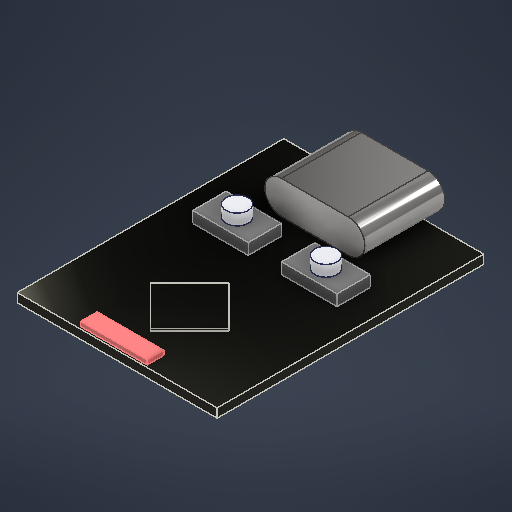
# Autodesk Inventor part: esp32-c3-supermini
Saved by Autodesk Inventor 2027.1 (Build 311270010, 270A)
## iProperties
Created: 2026-09-27
Part Number: esp32-c3-supermini
Material: 열가소성 수지
Document SubType Name: Modeling
Designer: work
Density: 1.28 g/cm^3
Appearance: 매끄러움 - 검은색
Author: work
Autodesk Inventor part; units mm, degrees
ref_plane "YZ Plane" through (0, 0, 0) normal (1, 0, 0) x (0, 1, 0)
ref_plane "XZ Plane" through (0, 0, 0) normal (0, 1, 0) x (-1, 0, 0)
sketch "스케치1" plane through (0, 0, 0) normal (0, 1, 0) x (-1, 0, 0)
  line L0 (0, 0) -> (18, 0)
  line L1 (18, 0) -> (18, -24)
  line L2 (18, -24) -> (0, -24)
  line L3 (0, -24) -> (0, 0)
  dimension "d0" = 18
  dimension "d1" = 24
  constraints: 8 end point, 2 parallel, 1 horizontal, 1 perpendicular
  measures "d0" distance of L1.end L2.end
  measures "d1" distance of L0.end L1.end
extrude "돌출1" add sketch "스케치1" along normal blind 0.8
ref_plane "작업 평면1" through (0, 0, -25) normal (0, 0, -1) x (-1, 0, 0)
sketch "스케치2" plane through (0, 0, -25) normal (0, 0, -1) x (-1, 0, 0)
  line L0 (6, 2.3) -> (12, 2.3) construction
  line L1 (6, 0.8) -> (12, 0.8)
  line L2 (12, 3.8) -> (6, 3.8)
  arc A0 (6, 3.8) -> (6, 0.8) centre (6, 2.3) ccw
  arc A1 (12, 0.8) -> (12, 3.8) centre (12, 2.3) ccw
  line L3 (0, 0.8) -> (18, 0.8) projected
  line L4 (6, 3.6) -> (12, 3.6)
  arc A2 (12, 1) -> (12, 3.6) centre (12, 2.3) ccw
  line L5 (12, 1) -> (6, 1)
  arc A3 (6, 3.6) -> (6, 1) centre (6, 2.3) ccw
  point P0 (0, 0)
  point P1 (9, 2.3)
  point P2 (4.5, 2.3)
  point P3 (13.5, 2.3)
  point P4 (9, 0.8)
  dimension "d5" = 3
  dimension "d6" = 9
  dimension "d7" = 0.2
  constraints: 12 end point, 10 point on circle, 4 centre point, 4 tangent, 3 midpoint, 2 parallel, 1 horizontal, 3 other
  measures "d5" distance between parallel lines of L1 L2
  measures "d6" distance of point (4.5, 2.3) point (13.5, 2.3)
  measures "d7" distance between parallel lines of L2 L4
extrude "돌출2" add sketch "스케치2" against normal blind 7 separate body
sketch "스케치3" plane through (0, 0, -18) normal (0, 0, 1) x (1, 0, 0)
  line L0 (-6, 3.8) -> (-12, 3.8) projected
  arc A0 (-6, 0.8) -> (-6, 3.8) centre (-6, 2.3) ccw projected
  line L1 (-6, 3.8) -> (-12, 3.8) projected
  arc A1 (-12, 3.8) -> (-12, 0.8) centre (-12, 2.3) ccw projected
  line L2 (-12, 0.8) -> (-6, 0.8) projected
  line L3 (-6, 1) -> (-12, 1) projected
  arc A2 (-12, 3.6) -> (-12, 1) centre (-12, 2.3) ccw projected
  line L4 (-12, 3.6) -> (-6, 3.6) projected
  arc A3 (-6, 1) -> (-6, 3.6) centre (-6, 2.3) ccw projected
  point P0 (0, 0)
extrude "돌출3" add sketch "스케치3" along normal blind 0.2 contours A0 L2 A1 L0 | L3 A2 L4 A3 bodies 2
sketch "스케치4" plane through (0, 0.8, 0) normal (0, 1, 0) x (1, 0, 0)
  line L0 (-9, 10.0711) -> (-12.5355, 6.5355)
  line L1 (-12.5355, 6.5355) -> (-9, 3)
  line L2 (-9, 3) -> (-5.4645, 6.5355)
  line L3 (-5.4645, 6.5355) -> (-9, 10.0711)
  line L4 (-9, 10.0711) -> (-4, 10.0711) construction
  line L5 (-18, 0) -> (0, 0) projected
  point P0 (-9, 0)
  point P1 (-9, 0)
  dimension "d12" = 135
  dimension "d13" = 5
  dimension "d14" = 3
  constraints: 10 end point, 2 equal length, 2 midpoint, 2 parallel, 1 horizontal, 1 perpendicular, 1 vertical alignment
  measures "d12" angle of L0 L4
  measures "d13" distance of L0.start L0.end
  measures "d14" distance of point (-9, 0) L1.end
extrude "돌출4" add sketch "스케치4" along normal blind 0.2 bodies 1
sketch "스케치5" plane through (0, 0.8, 0) normal (0, 1, 0) x (1, 0, 0)
  line L0 (-5.4645, 6.5355) -> (-9, 10.0711) projected
  line L1 (-9, 10.0711) -> (-9, 18) construction
  line L2 (-12, 18) -> (-6, 18) projected
  line L3 (-7.5, 16.3) -> (-2.5, 16.3)
  line L4 (-2.5, 16.3) -> (-2.5, 13.3)
  line L5 (-2.5, 13.3) -> (-7.5, 13.3)
  line L6 (-7.5, 13.3) -> (-7.5, 16.3)
  line L7 (-6, 17.8) -> (-4.5, 17.8) projected
  line L8 (-10.5, 16.3) -> (-15.5, 16.3)
  line L9 (-15.5, 16.3) -> (-15.5, 13.3)
  line L10 (-15.5, 13.3) -> (-10.5, 13.3)
  line L11 (-10.5, 13.3) -> (-10.5, 16.3)
  point P0 (0, 0)
  point P1 (-7.5, 14.8)
  point P2 (-5, 16.3)
  point P3 (-10.5, 14.8)
  point P4 (-13, 16.3)
  dimension "d17" = 5
  dimension "d18" = 3
  dimension "d19" = 1.5
  dimension "d20" = 1.5
  constraints: 18 end point, 6 symmetric about line, 3 midpoint, 2 parallel, 1 horizontal, 1 perpendicular
  measures "d17" distance of L4.end L5.end
  measures "d18" distance of L3.end L4.end
  measures "d19" distance from line of L1 point (-7.5, 14.8)
  measures "d20" distance from line of L7 point (-5, 16.3)
extrude "돌출5" add sketch "스케치5" along normal blind 1 separate body
sketch "스케치6" plane through (0, 1.8, 0) normal (0, 1, 0) x (1, 0, 0)
  line L0 (-12, 17.8) -> (-6, 17.8) projected
  line L1 (-9, 17.8) -> (-9, 10.0711) construction
  circle A0 centre (-5, 14.8) radius 1
  line L2 (-7.5, 16.3) -> (-7.5, 13.3) projected
  line L3 (-2.5, 16.3) -> (-7.5, 16.3) projected
  circle A1 centre (-13, 14.8) radius 1
  point P0 (0, 0)
  point P1 (-7.5, 14.8)
  point P2 (-5, 16.3)
  dimension "d23" = 2
  constraints: 3 midpoint, 2 centre point, 2 end point, 1 horizontal alignment, 1 symmetric about line, 1 vertical alignment, 1 other
  measures "d23" diameter of A0
extrude "돌출6" add sketch "스케치6" along normal blind 1 separate body
sketch "스케치7" plane through (0, 0.8, 0) normal (0, 1, 0) x (1, 0, 0)
  line L0 (-11.5, 1.7) -> (-6.5, 1.7)
  line L1 (-6.5, 1.7) -> (-6.5, 0.2)
  line L2 (-6.5, 0.2) -> (-11.5, 0.2)
  line L3 (-11.5, 0.2) -> (-11.5, 1.7)
  line L4 (-18, 0) -> (0, 0) projected
  line L5 (-11.5, 1.7) -> (-12.5, 1.7)
  line L6 (-12.5, 1.7) -> (-12.5, 0.2)
  line L7 (-12.5, 0.2) -> (-11.5, 0.2)
  line L8 (-11.5, 0.2) -> (-11.5, 1.7)
  point P0 (-9, 3)
  point P1 (-9, 1.7)
  dimension "d26" = 1.5
  dimension "d27" = 5
  dimension "d28" = 0.2
  dimension "d29" = 1
  constraints: 16 end point, 4 parallel, 2 horizontal, 2 perpendicular, 1 midpoint, 1 point on line, 1 vertical alignment
  measures "d26" distance of L0.end L1.end
  measures "d27" distance of L0.start L0.end
  measures "d28" distance between parallel lines of L4 L2
  measures "d29" distance of L0.start L5.end
extrude "돌출7" add sketch "스케치7" along normal blind 0.4 separate body
